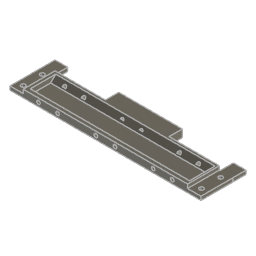
Front-Panel (Autodesk Fusion 360 design; units mm, degrees)
part number: 2026-04-13-11-13-41-725
Autodesk Fusion 360 part; units mm, degrees
sketch "Sketch1" plane through (0, 0, 0) normal (0, 0, 1) x (1, 0, 0)
  line L0 (-75, 25) -> (-75, 0)
  line L1 (-75, 0) -> (75, 0)
  line L2 (75, 0) -> (75, 25)
  line L3 (25, 35.5) -> (-25, 35.5)
  line L4 (-25, 35.5) -> (-25, 25)
  line L5 (-65, 23) -> (65, 23)
  line L6 (-25, 25) -> (-65, 25)
  line L7 (65, 0) -> (65, 23)
  line L8 (-65, 0) -> (-65, 23)
  circle A0 centre (-70, 20.5) radius 1.65
  circle A1 centre (-70, 5.5) radius 1.65
  circle A2 centre (70, 5.5) radius 1.65
  circle A3 centre (70, 20.5) radius 1.65
  line L9 (-64.5, 23) -> (-64.5, 0)
  line L10 (64.5, 23) -> (64.5, 0)
  line L11 (63, 23) -> (63, 22.8583)
  line L12 (63, 22.8583) -> (63, 0)
  line L13 (65, 25) -> (25, 25)
  line L14 (25, 25) -> (25, 35.5)
  line L15 (-62, 23) -> (-62, 0)
  line L16 (-62, 3) -> (63, 3)
  line L17 (64.5, 23) -> (64.5, 25)
  line L18 (-64.5, 23) -> (-64.5, 25)
  line L19 (75, 25) -> (75, 35.5)
  line L20 (75, 35.5) -> (65, 35.5)
  line L21 (65, 35.5) -> (65, 25)
  line L22 (-75, 25) -> (-75, 35.5)
  line L23 (-75, 35.5) -> (-65, 35.5)
  line L24 (-65, 35.5) -> (-65, 25)
  dimension "d12" = 3.3
  dimension "d14" = 3.3
  constraint perpendicular L0 L6
  constraint parallel L0 L2
  constraint perpendicular L4 L6
  constraint perpendicular L2 L5
  constraint coincident L1 L7.start
  constraint perpendicular L5 L7
  constraint coincident L1 L8.start
  constraint perpendicular L5 L8
  constraint coincident L5 L9.start
  constraint coincident L1 L9.end
  constraint perpendicular L1 L9
  constraint coincident L5 L10.start
  constraint perpendicular L5 L10
  constraint parallel L10 L11
  constraint coincident L1 L12.end
  constraint perpendicular L1 L12
  constraint coincident L3 L14.end
  constraint perpendicular L3 L14
  constraint coincident L5 L15.start
  constraint coincident L1 L15.end
  constraint perpendicular L1 L15
  constraint coincident L15 L16.start
  constraint coincident L12 L16.end
  constraint perpendicular L12 L16
  constraint coincident L13 L17.end
  constraint perpendicular L13 L17
  constraint coincident L6 L18.end
  constraint perpendicular L6 L18
  constraint perpendicular L19 L20
  constraint perpendicular L13 L21
  constraint perpendicular L6 L22
  constraint perpendicular L4 L23
  constraint perpendicular L6 L24
  measures "d12" diameter of A0
  measures "d14" diameter of A3
extrude "Extrude5" add sketch "Sketch1" along normal blind 3 contours L0 L1 L5 L6 L8 L18 L22 L23 L24 | L1 L5 L8 L9 | L1 L5 L7 L10 | L1 L2 L5 L7 L13 L17 L19 L20 L21 makes body 1 at (-68.3333, 32, 0) makes body 2 at (71.6667, 28.5, 0)
extrude "Extrude7" add sketch "Sketch1" along normal blind 2 contours L5 L11 L12 L15 L16 bodies 1 2 makes body 3
extrude "Extrude6" add sketch "Sketch1" along normal blind 6 contours L1 L5 L9 L15 | L1 L12 L15 L16 | L3 L4 L5 L6 L13 L14 L17 L18 | L1 L5 L10 L11 L12 bodies 1 2
sketch "Sketch5" plane through (63, 0, 0) normal (-1, 0, 0) x (0, -1, 0)
  line L0 (-23, 0) -> (-3, 0)
  line L1 (-3, 0) -> (-3, 6)
  line L2 (-3, 6) -> (-23, 6)
  line L3 (-23, 6) -> (-23, 0)
  line L4 (-3, 6) -> (-7, 2)
  line L5 (-23, 6) -> (-19, 2)
  line L6 (-3, 6) -> (-3, 2)
  line L7 (-7, 2) -> (-3, 2)
  line L8 (-23, 6) -> (-23, 2)
  line L9 (-23, 2) -> (-19, 2)
  constraint coincident L1.end L2.start
  constraint coincident L2.end L3.start
  constraint coincident L1 L6.end
  constraint perpendicular L6 L7
  constraint coincident L3 L8.end
  constraint perpendicular L8 L9
extrude "Extrude8" add sketch "Sketch5" along normal blind 125 contours L3 L5 L8 L9 | L1 L4 L6 L7 bodies 1 3
sketch "Sketch3" plane through (0, 35.5, 0) normal (0, 1, 0) x (-1, 0, 0)
  line L0 (-25, 0) -> (25, 0)
  line L1 (25, 0) -> (25, 6)
  line L2 (25, 6) -> (-25, 6)
  line L3 (-25, 6) -> (-25, 0)
  circle A0 centre (7.5, 3) radius 1.425
  circle A1 centre (-7.5, 3) radius 1.425
  dimension "d34" = 2.85
  measures "d34" diameter of A1
extrude "Extrude9" cut sketch "Sketch3" against normal blind 15 contours A0 | A1 bodies 1
sketch "Sketch4" plane through (0, 0, 0) normal (0, -1, 0) x (1, 0, 0)
  line L0 (-75, 0) -> (75, 0)
  line L1 (75, 0) -> (75, 3)
  line L2 (75, 3) -> (64.5, 3)
  line L3 (64.5, 3) -> (64.5, 6)
  line L4 (64.5, 6) -> (-64.5, 6)
  line L5 (-64.5, 6) -> (-64.5, 3)
  line L6 (-64.5, 3) -> (-75, 3)
  line L7 (-75, 3) -> (-75, 0)
  circle A0 centre (-7.5, 3) radius 1.425
  circle A1 centre (7.5, 3) radius 1.425
  circle A2 centre (-37.5, 3) radius 1.425
  circle A3 centre (37.5, 3) radius 1.425
  circle A4 centre (-52.5, 3) radius 1.425
  circle A5 centre (52.5, 3) radius 1.425
  circle A6 centre (-37.5, 3) radius 1.425
  dimension "d42" = 2.85
  measures "d42" diameter of A5
extrude "Extrude10" cut sketch "Sketch4" against normal blind 6 contours A0 | A1 | A2 A6 | A3 | A4 | A5 bodies 1
sketch "Sketch6" plane through (0, 25, 0) normal (0, 1, 0) x (-1, 0, 0)
  line L0 (25, 0) -> (65, 0)
  line L1 (65, 0) -> (65, 3)
  line L2 (65, 3) -> (64.5, 3)
  line L3 (64.5, 3) -> (64.5, 6)
  line L4 (64.5, 6) -> (25, 6)
  line L5 (25, 6) -> (25, 0)
  circle A0 centre (37.5, 3) radius 1.425
  circle A1 centre (52.5, 3) radius 1.425
  circle A2 centre (-52.5, 3) radius 1.425
  circle A3 centre (-37.5, 3) radius 1.425
extrude "Extrude11" cut sketch "Sketch6" against normal blind 5 contours A0 | A1 | A2 | A3 bodies 1
